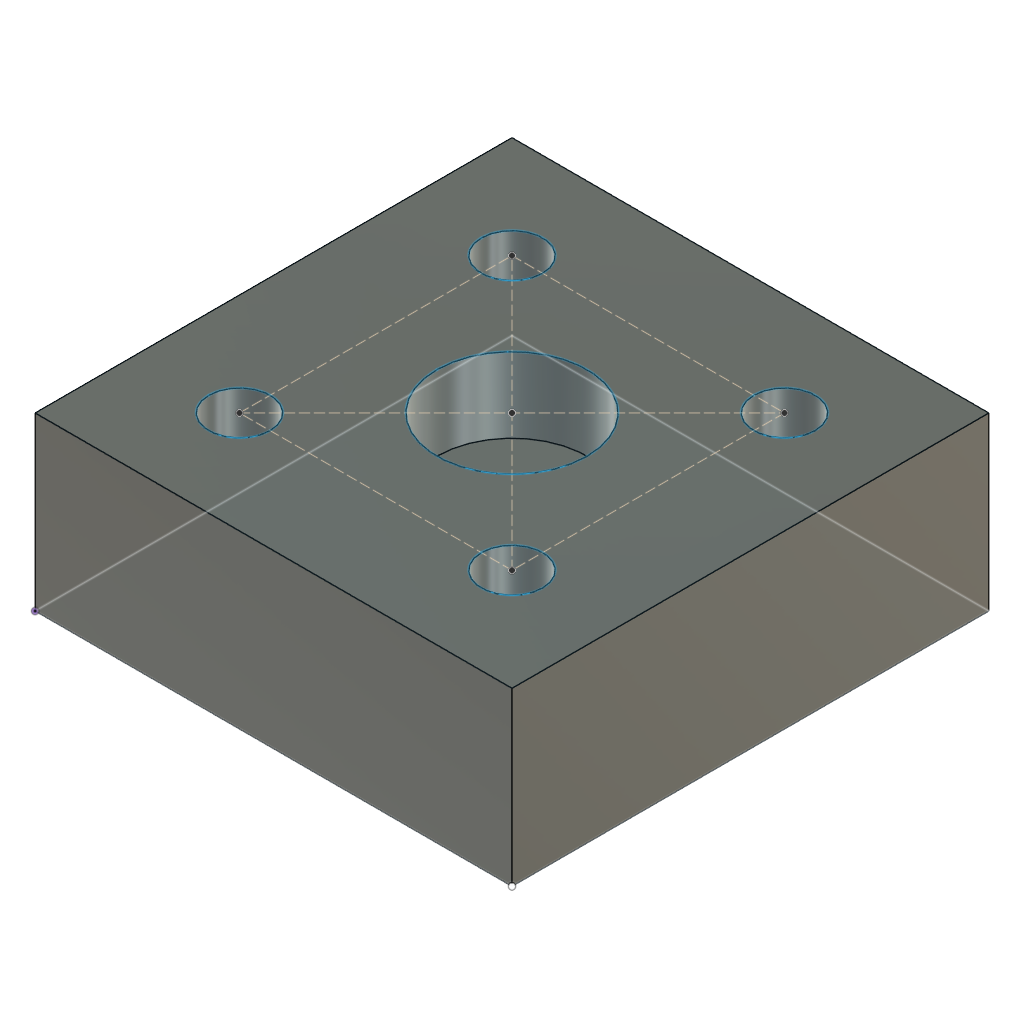
bearing mount (Autodesk Fusion 360 design; units mm, degrees)
part number: 2026-11-17-15-41-37-183
Autodesk Fusion 360 part; units mm, degrees
sketch "Sketch1" plane through (0, 0, 0) normal (0, 0, 1) x (1, 0, 0)
  line L0 (0, 0) -> (70, 0)
  line L1 (0, 0) -> (0, 70)
  line L2 (0, 70) -> (70, 70)
  line L3 (70, 70) -> (70, 0)
  dimension "d11" = 70
  dimension "d12" = 70
  dimension "d13" = 70
  dimension "d14" = 70
  constraint coincident L0.start L1.start
  constraint horizontal L0
  constraint perpendicular L0 L1
  constraint perpendicular L1 L2
  constraint perpendicular L0 L3
  measures "d11" distance of L0.start L0.end
  measures "d12" distance of L0.start L1.end
  measures "d13" distance of L1.end L2.end
  measures "d14" distance of L2.end L0.end
extrude "Extrude1" add sketch "Sketch1" along normal blind 25.18
sketch "Sketch2" plane through (0, 0, 25.18) normal (0, 0, 1) x (-1, 0, 0)
  line L0 (0, 0) -> (-70, 0)
  line L1 (-70, 0) -> (-70, -70)
  line L2 (-70, -70) -> (0, -70)
  line L3 (0, -70) -> (0, 0)
  circle A0 centre (-35, -35) radius 11.0163
  line L4 (-55, -15) -> (-15, -15) construction
  line L5 (-15, -15) -> (-15, -55) construction
  line L6 (-15, -55) -> (-55, -55) construction
  line L7 (-55, -55) -> (-55, -15) construction
  line L8 (-55, -15) -> (-15, -55) construction
  line L9 (-15, -15) -> (-55, -55) construction
  circle A1 centre (-15, -55) radius 4.5
  circle A2 centre (-55, -55) radius 4.5
  circle A3 centre (-15, -15) radius 4.5
  circle A4 centre (-55, -15) radius 4.5
  point P0 (-35, -35)
  dimension "d18" = 22.0325
  dimension "d19" = 40
  dimension "d20" = 40
  dimension "d21" = 9
  dimension "d22" = 9
  dimension "d23" = 9
  dimension "d24" = 9
  constraint horizontal L4
  constraint perpendicular L4 L5
  constraint parallel L4 L6
  constraint parallel L5 L7
  constraint coincident L8 P0
  constraint coincident L9 P0
  constraint coincident P0 A0.centre
  constraint coincident L5.end L6.start
  constraint coincident L6.end L7.start
  constraint coincident L4.end L5.start
  constraint coincident L4.start L7.end
  measures "d18" diameter of A0
  measures "d19" distance of L5.end L6.end
  measures "d20" distance of L4.end L5.end
  measures "d21" diameter of A1
  measures "d22" diameter of A2
  measures "d23" diameter of A3
  measures "d24" diameter of A4
extrude "Extrude2" cut sketch "Sketch2" against normal blind 11 contours A0
extrude "Extrude3" cut sketch "Sketch2" against normal through all contours A1 | A2 | A3 | A4
equation "mountlength = 70 mm"
equation "mountwidth = 70 mm"
equation "mountthickness = 25.18 mm"
equation "bearingdiameter = 22.0325 mm"
equation "bearingdepth = 11 mm"
equation "bottomjournal = 10 mm"
equation "mountingholes = 9 mm"
equation "coverdiameter = 42 mm"
equation "coverthickness = 2 mm"
equation "covercenteropening = 16 mm"
equation "d11 = mountlength"
equation "d12 = mountwidth"
equation "d13 = mountlength"
equation "d14 = mountwidth"
equation "d15 = mountthickness"
equation "d18 = bearingdiameter"
equation "d21 = mountingholes"
equation "d22 = mountingholes"
equation "d23 = mountingholes"
equation "d24 = mountingholes"
